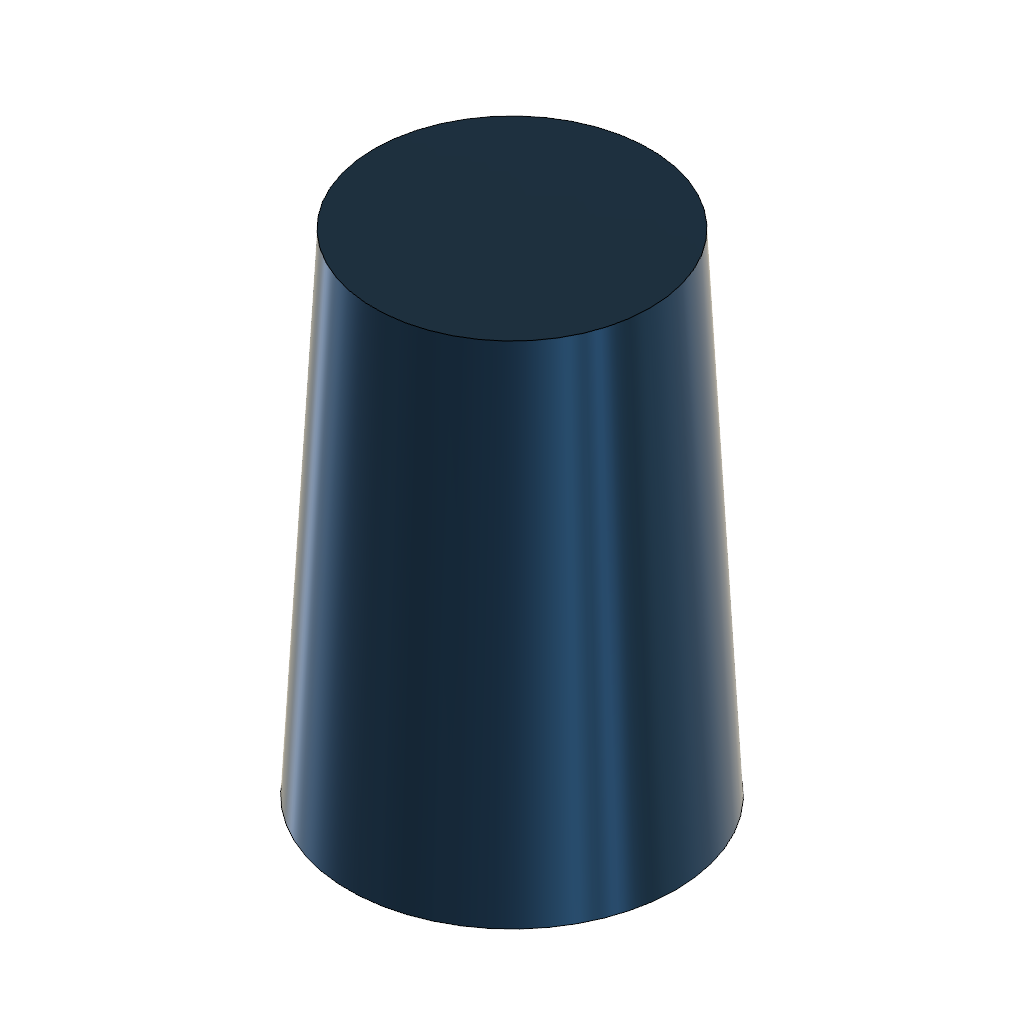
vendor_ZeroAngleLimit27mmMinus3deg (Autodesk Fusion 360 design; units mm, degrees)
Autodesk Fusion 360 part; units mm, degrees
sketch "Independent base circle" plane through (0, 0, 0) normal (0, 0, 1) x (1, 0, 0)
  circle A0 centre (0, 0) radius 9
extrude "Independent tapered extrusion" add sketch "Independent base circle" along normal blind 27 draft -3
equation "frustumHeight = 27 mm" comment "Independent tapered extrusion driving height"
equation "d2 = frustumHeight"
